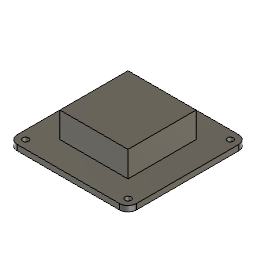
FocusLensPlate Resin Blank (Autodesk Fusion 360 design; units mm, degrees)
Autodesk Fusion 360 part; units mm, degrees
sketch "Sketch2" plane through (0, 0, 0) normal (0, 0, 1) x (1, 0, 0)
  line L0 (-20, 20) -> (20, 20)
  line L1 (20, 20) -> (20, -20)
  line L2 (20, -20) -> (-20, -20)
  line L3 (-20, -20) -> (-20, 20)
  line L4 (-20, 20) -> (20, -20) construction
  line L5 (20, 20) -> (-20, -20) construction
  line L6 (-35, 35) -> (35, 35)
  line L7 (35, 35) -> (35, -35)
  line L8 (35, -35) -> (-35, -35)
  line L9 (-35, -35) -> (-35, 35)
  line L10 (-35, 35) -> (35, -35) construction
  line L11 (35, 35) -> (-35, -35) construction
  line L12 (-30, 30) -> (30, 30)
  line L13 (30, 30) -> (30, -30)
  line L14 (30, -30) -> (-30, -30)
  line L15 (-30, -30) -> (-30, 30)
  line L16 (-30, 30) -> (30, -30) construction
  line L17 (30, 30) -> (-30, -30) construction
  circle A0 centre (-30, -30) radius 1.75
  circle A1 centre (30, -30) radius 1.75
  circle A2 centre (30, 30) radius 1.75
  circle A3 centre (-30, 30) radius 1.75
  line L18 (-17, 17) -> (17, 17)
  line L19 (17, 17) -> (17, -17)
  line L20 (17, -17) -> (-17, -17)
  line L21 (-17, -17) -> (-17, 17)
  line L22 (-17, 17) -> (17, -17) construction
  line L23 (17, 17) -> (-17, -17) construction
  dimension "d5" = 40
  dimension "d6" = 40
  dimension "d7" = 70
  dimension "d8" = 70
  dimension "d9" = 60
  dimension "d10" = 60
  dimension "d11" = 3.5
  dimension "d13" = 360
  dimension "d27" = 34
  dimension "d28" = 34
  constraint horizontal L0
  constraint perpendicular L0 L1
  constraint parallel L0 L2
  constraint parallel L1 L3
  constraint coincident L4 origin
  constraint coincident L5 origin
  constraint horizontal L6
  constraint perpendicular L6 L7
  constraint parallel L6 L8
  constraint parallel L7 L9
  constraint coincident L10 origin
  constraint coincident L11 origin
  constraint horizontal L12
  constraint perpendicular L12 L13
  constraint parallel L12 L14
  constraint parallel L13 L15
  constraint coincident L16 origin
  constraint coincident L17 origin
  constraint coincident L14.end L15.start
  constraint horizontal L18
  constraint perpendicular L18 L19
  constraint parallel L18 L20
  constraint parallel L19 L21
  constraint coincident L22 origin
  constraint coincident L23 origin
  measures "d5" distance of L1.end L2.end
  measures "d6" distance of L0.end L1.end
  measures "d7" distance of L7.end L8.end
  measures "d8" distance of L6.end L7.end
  measures "d9" distance of L13.end L14.end
  measures "d10" distance of L12.end L13.end
  measures "d11" diameter of A0
  measures "d27" distance of L19.end L20.end
  measures "d28" distance of L18.end L19.end
extrude "Extrude1" add sketch "Sketch2" against normal blind 3.3 contours L0 L1 L2 L3 | L6 L7 L8 L9 | L12 L13 L14 L15 A0 A1 A2 A3 | L18 L19 L20 L21
extrude "Extrude2" add sketch "Sketch2" along normal blind 15 contours L0 L1 L2 L3 | L18 L19 L20 L21
fillet "Fillet3" radius 5 4 edges at (35, 35, -1.65) (-35, 35, -1.65) (35, -35, -1.65) (-35, -35, -1.65)
equation "d14 = ( -5 * 0.66 ) * 1 mm"
